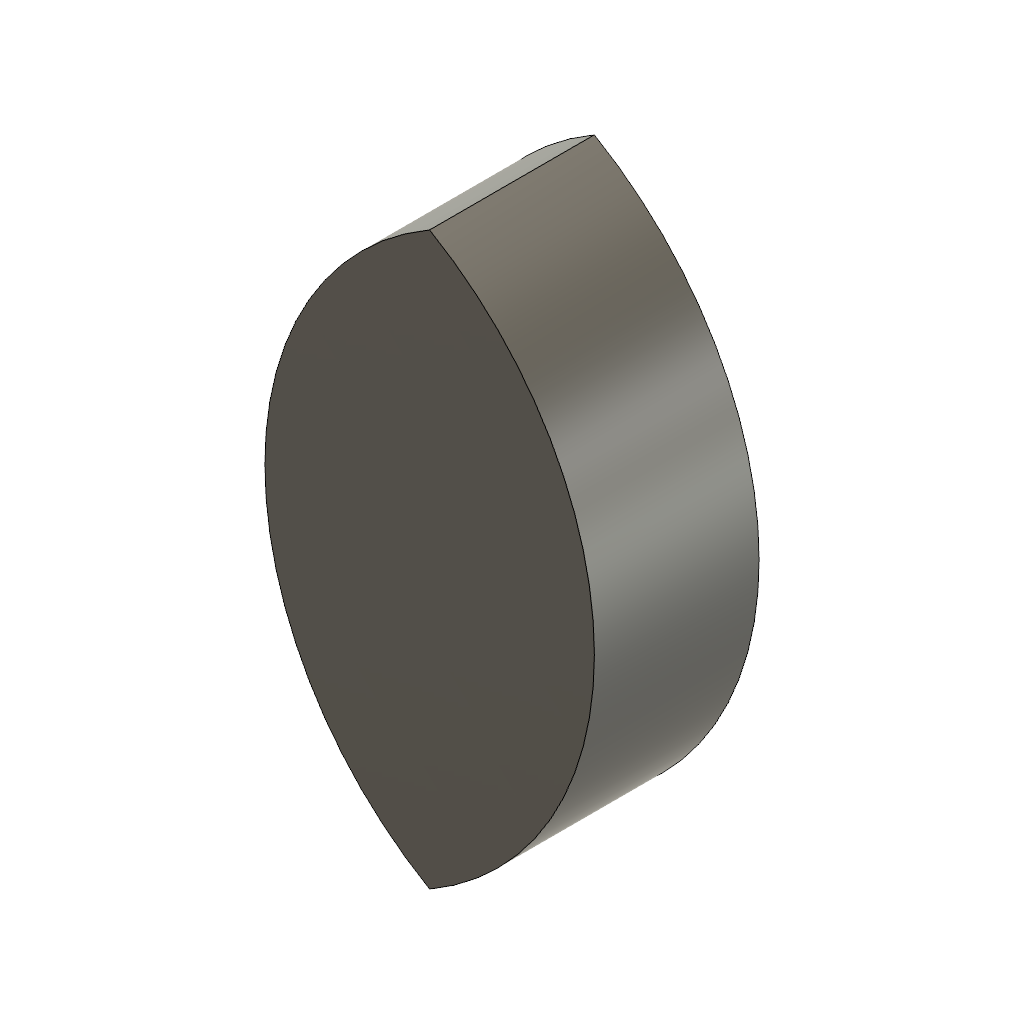
offset_xy_circle_lens (Autodesk Fusion 360 design; units mm, degrees)
part number: 2026-10-21-12-26-12-813
Autodesk Fusion 360 part; units mm, degrees
ref_plane "WorkPlane1" through (0, 0, 12.5) normal (0, 0, 1) x (1, 0, 0)
sketch "TrimmedProfileSources" plane through (0, 0, 12.5) normal (0, 0, 1) x (1, 0, 0)
  circle A0 centre (-10, 0) radius 20
  circle A1 centre (10, 0) radius 20
extrude "SelectedTrimmedProfile" add sketch "TrimmedProfileSources" along normal blind 10 contours A0 A1 picked at (-3.2589, 0.9936)
